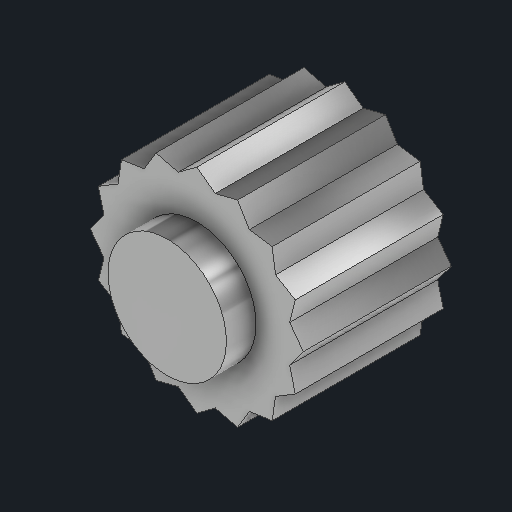
# Autodesk Inventor part: thumbscrew_small
Saved by Autodesk Inventor 2027.1 (Build 311270010, 270A)
## iProperties
Created: 2026-11-04
Part Number: thumbscrew_small
Material: Generic
Description: Small knurled thumbscrew (setting circle / polar scope), head only
Document SubType Name: Modeling
Designer: Claude (from photos)
Density: 1 g/cm^3
Appearance: Stainless Steel - Bright
Author: alexg
Autodesk Inventor part; units mm, degrees
ref_plane "YZ Plane" through (0, 0, 0) normal (1, 0, 0) x (0, 1, 0)
ref_plane "Work Plane1" through (0, 0, -6) normal (0, 0, 1) x (1, 0, 0)
sketch "Knurled head sketch" plane through (0, 0, -6) normal (0, 0, 1) x (1, 0, 0)
  line L0 (3.6, 0) -> (3.1385, 0.6243)
  line L1 (3.1385, 0.6243) -> (3.326, 1.3777)
  line L2 (3.326, 1.3777) -> (2.6607, 1.7778)
  line L3 (2.6607, 1.7778) -> (2.5456, 2.5456)
  line L4 (2.5456, 2.5456) -> (1.7778, 2.6607)
  line L5 (1.7778, 2.6607) -> (1.3777, 3.326)
  line L6 (1.3777, 3.326) -> (0.6243, 3.1385)
  line L7 (0.6243, 3.1385) -> (0, 3.6)
  line L8 (0, 3.6) -> (-0.6243, 3.1385)
  line L9 (-0.6243, 3.1385) -> (-1.3777, 3.326)
  line L10 (-1.3777, 3.326) -> (-1.7778, 2.6607)
  line L11 (-1.7778, 2.6607) -> (-2.5456, 2.5456)
  line L12 (-2.5456, 2.5456) -> (-2.6607, 1.7778)
  line L13 (-2.6607, 1.7778) -> (-3.326, 1.3777)
  line L14 (-3.326, 1.3777) -> (-3.1385, 0.6243)
  line L15 (-3.1385, 0.6243) -> (-3.6, 0)
  line L16 (-3.6, 0) -> (-3.1385, -0.6243)
  line L17 (-3.1385, -0.6243) -> (-3.326, -1.3777)
  line L18 (-3.326, -1.3777) -> (-2.6607, -1.7778)
  line L19 (-2.6607, -1.7778) -> (-2.5456, -2.5456)
  line L20 (-2.5456, -2.5456) -> (-1.7778, -2.6607)
  line L21 (-1.7778, -2.6607) -> (-1.3777, -3.326)
  line L22 (-1.3777, -3.326) -> (-0.6243, -3.1385)
  line L23 (-0.6243, -3.1385) -> (0, -3.6)
  line L24 (0, -3.6) -> (0.6243, -3.1385)
  line L25 (0.6243, -3.1385) -> (1.3777, -3.326)
  line L26 (1.3777, -3.326) -> (1.7778, -2.6607)
  line L27 (1.7778, -2.6607) -> (2.5456, -2.5456)
  line L28 (2.5456, -2.5456) -> (2.6607, -1.7778)
  line L29 (2.6607, -1.7778) -> (3.326, -1.3777)
  line L30 (3.326, -1.3777) -> (3.1385, -0.6243)
  line L31 (3.1385, -0.6243) -> (3.6, 0)
  constraints: 64 end point
extrude "Knurled head" add sketch "Knurled head sketch" along normal blind 5
ref_plane "Work Plane2" through (0, 0, -1) normal (0, 0, 1) x (1, 0, 0)
sketch "Neck sketch" plane through (0, 0, -1) normal (0, 0, 1) x (1, 0, 0)
  circle A0 centre (0, 0) radius 2
  constraints: 1 centre point
extrude "Neck" add sketch "Neck sketch" along normal blind 1
body "Solid1"
